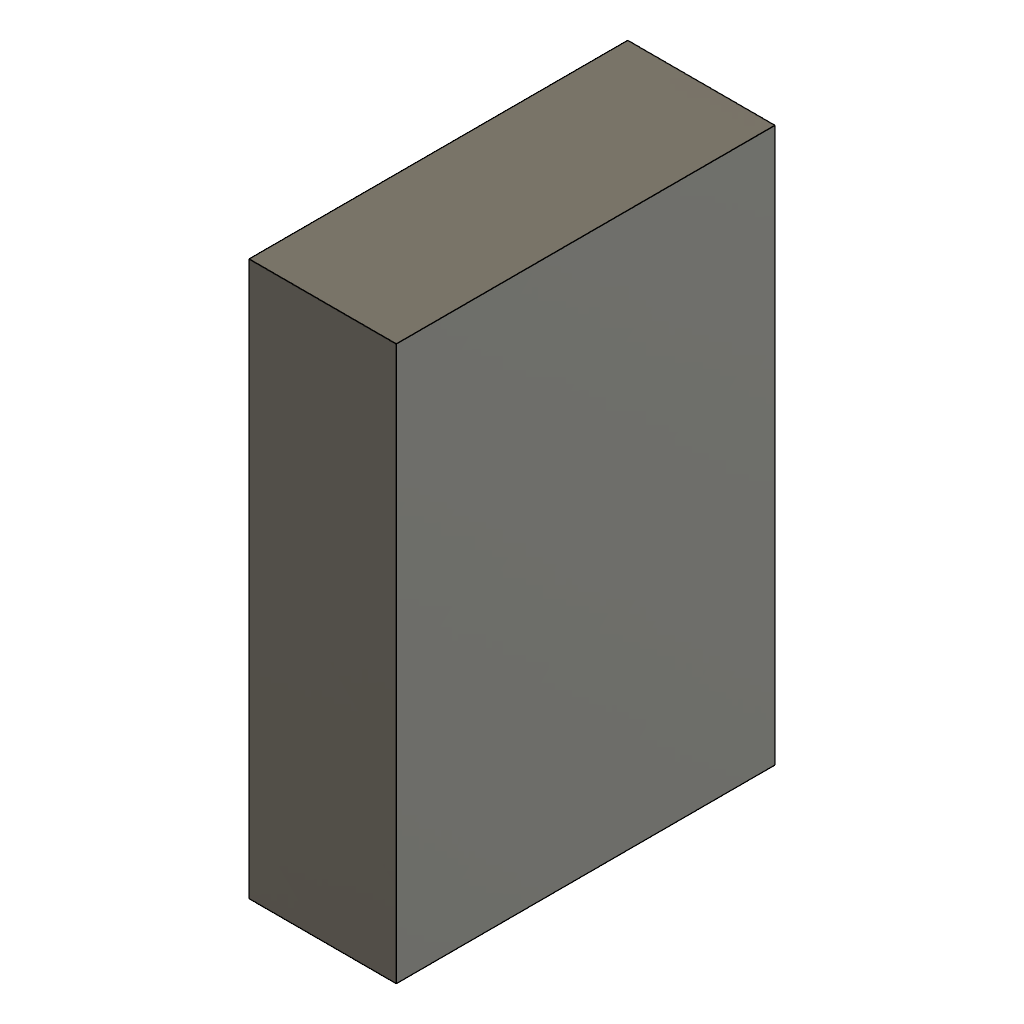
datum-yz (Autodesk Fusion 360 design; units mm, degrees)
part number: 2026-11-22-22-06-09-751
Autodesk Fusion 360 part; units mm, degrees
sketch "Sketch1" plane through (0, 0, 0) normal (1, 0, 0) x (0, 0, -1)
  line L0 (0, 0) -> (16.2, 0)
  line L1 (16.2, 0) -> (16.2, 23.7)
  line L2 (16.2, 23.7) -> (0, 23.7)
  line L3 (0, 23.7) -> (0, 0)
extrude "ControlledBoss" add sketch "Sketch1" along normal blind 6.3
